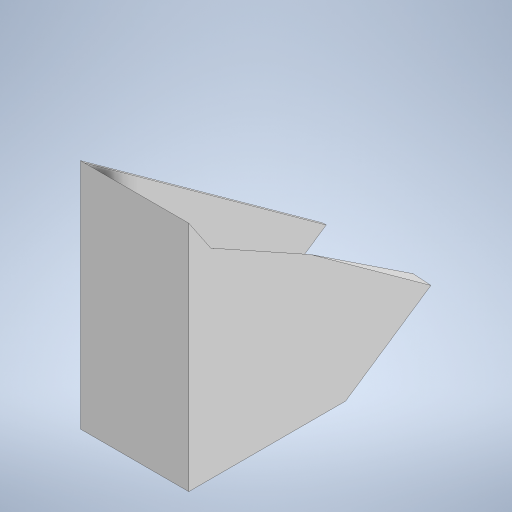
# Autodesk Inventor part: cale
Saved by Autodesk Inventor 2024.3 (Build 283343000, 343)
## iProperties
Created: 2025-04-04
Part Number: cale
Material: Générique
Document SubType Name: Modeling
Designer: abouabdellah
Density: 1 g/cm^3
Appearance: Par défaut
Author: abouabdellah
Autodesk Inventor part; units mm, degrees
ref_plane "YZ Plane" through (0, 0, 0) normal (1, 0, 0) x (0, 1, 0)
ref_plane "XZ Plane" through (0, 0, 0) normal (0, 1, 0) x (-1, 0, 0)
ref_plane "XY Plane" through (0, 0, 0) normal (0, 0, 1) x (1, 0, 0)
sketch "Esquisse1" plane through (0, 0, 0) normal (1, 0, 0) x (0, 1, 0)
  line L0 (0, 30.978) -> (0, -41.801)
  line L1 (0, -41.801) -> (124.3426, 42.0972)
  line L2 (124.3426, 42.0972) -> (0, 42.0972)
  line L3 (0, 42.0972) -> (0, 30.978)
  point P0 (0, 0)
  dimension "d6" = 150
  constraints: 8 end point, 2 perpendicular, 1 point on line, 1 vertical
  measures "d6" distance of L0.end L1.end
extrude "Extrusion1" add sketch "Esquisse1" along normal blind 56
sketch "Esquisse3" plane through (56, 124.3426, 42.0972) normal (0, 0.5593216, -0.8289508) x (-1, 0, 0)
  line L0 (56, 0) -> (0, 0) projected
  line L1 (0, -150) -> (0, 0) projected
  line L2 (0, 0) -> (0, -150)
  line L3 (0, -150) -> (20, -150)
  line L4 (56, -150) -> (0, -150) projected
  line L5 (20, -150) -> (0, 0)
  point P0 (56, -126.6198)
  dimension "d3" = 20
  constraints: 6 end point, 1 collinear, 1 point on line
  measures "d3" distance of L1.start L3.end
extrude "Extrusion2" add sketch "Esquisse3" along normal blind 56
sketch "Esquisse5" plane through (36, 0, -41.801) normal (-0.9912279, 0.1095572, 0.073922) x (0, -0.5593216, 0.8289508)
  line L0 (-56, 0) -> (-56, 151.3275) projected
  line L1 (0, 151.3275) -> (0, 0) projected
  line L2 (0, 151.3275) -> (-56, 151.3275) projected
  line L3 (-56, 0) -> (-56, 151.3275) projected
  line L4 (0, 0) -> (-56, 0) projected
  line L5 (-56, 0) -> (-56, 151.3275)
  line L6 (0, 151.3275) -> (-56, 0)
  point P0 (34.651, 18.4172)
  constraints: 4 end point, 1 collinear
extrude "Extrusion3" cut sketch "Esquisse5" against normal blind 20 contours L0 L2 L6
chamfer "Chanfrein1" distance 10 angle 45 1 edges at (46, 77.8323, -23.0625)
fillet "Congé1" radius 10 1 edges at (44.0959, 63.0125, -26.6304)
sketch "Esquisse7" plane through (0, 0, 0) normal (-1, 0, 0) x (0, 0, 1)
  line L0 (-41.801, 0) -> (42.0972, 124.3426) projected
  line L1 (42.0972, 0) -> (-41.801, 0) projected
  line L2 (42.0972, 124.3426) -> (42.0972, 0) projected
  line L3 (-41.801, 0) -> (-87.4114, 30.7749) projected
  line L4 (-41.801, 0) -> (-87.4114, 30.7749)
  line L5 (-87.4114, 30.7749) -> (42.0972, 124.3426)
  line L6 (-87.4114, 30.7749) -> (-23.2301, 77.1447) projected
  line L7 (19.5055, 90.8602) -> (-41.801, 0) projected
  line L8 (42.0972, 124.3426) -> (-41.801, 0)
  point P0 (0, 0)
  constraints: 6 end point, 3 collinear
extrude "Extrusion5" add sketch "Esquisse7" along normal blind 2
